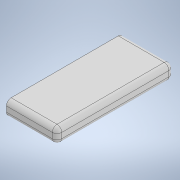
# Autodesk Inventor part: distantier
Saved by Autodesk Inventor 2022.6 (Build 266554000, 554)
## iProperties
Created: 2026-03-13
Part Number: distantier
Material: Generic
Document SubType Name: Modeling
Designer: Dragos Macovei
Density: 1 g/cm^3
Appearance: Default
Author: Dragos Macovei
Autodesk Inventor part; units mm, degrees
ref_plane "YZ Plane" through (0, 0, 0) normal (1, 0, 0) x (0, 1, 0)
ref_plane "XZ Plane" through (0, 0, 0) normal (0, 1, 0) x (-1, 0, 0)
ref_plane "XY Plane" through (0, 0, 0) normal (0, 0, 1) x (1, 0, 0)
sketch "Sketch1" plane through (0, 0, 0) normal (0, 1, 0) x (-1, 0, 0)
  line L0 (0, 0) -> (21.5, 0)
  line L1 (21.5, 0) -> (21.5, 49.5)
  line L2 (21.5, 49.5) -> (0, 49.5)
  line L3 (0, 49.5) -> (0, 0)
  dimension "d0" = 21.5
  dimension "d1" = 49.5
  constraints: 8 end point, 2 parallel, 1 horizontal, 1 perpendicular
  measures "d0" distance of L2.end L1.end
  measures "d1" distance of L1.end L0.end
extrude "Extrusion1" add sketch "Sketch1" along normal blind 6.3
fillet "Fillet1" radius 2 2 edges at (0, 3.15, 49.5) (0, 3.15, 0)
fillet "Fillet2" radius 2 10 edges at (-0.5858, 6.3, 0.5858) (-11.75, 6.3, 0) (-0.5858, 6.3, 48.9142) (-11.75, 6.3, 49.5) (0, 6.3, 24.75) (-0.5858, 0, 0.5858) (-11.75, 0, 0) (-0.5858, 0, 48.9142) (-11.75, 0, 49.5) (0, 0, 24.75)
body "Solid1"
